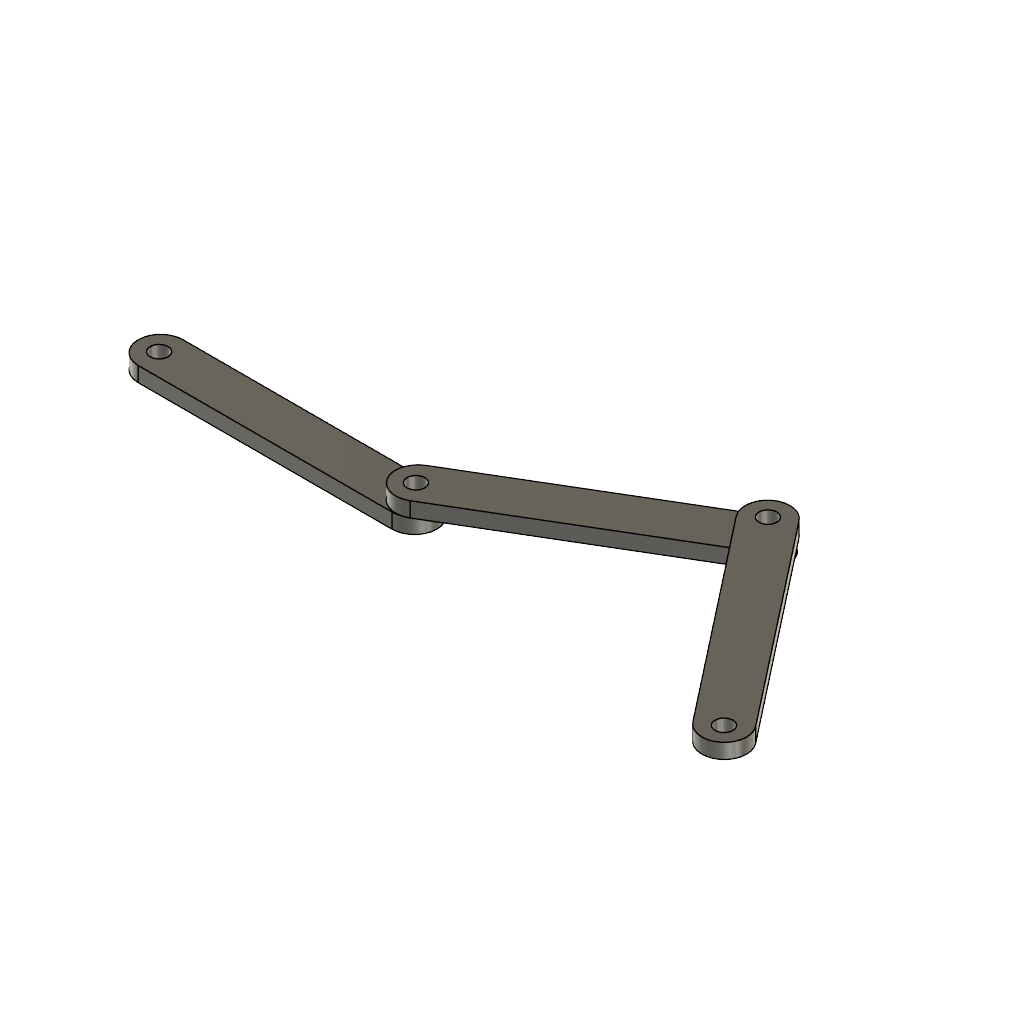
Rib (Autodesk Fusion 360 archive; units mm, degrees)
design "제목 없음"
part number: 2026-10-09-12-04-33-957
part number: 2026-10-10-00-51-56-388
Autodesk Fusion 360 part; units mm, degrees
sketch "스케치1" plane through (0, 0, 0) normal (0, 0, 1) x (1, 0, 0)
  line L0 (0, 0) -> (100, 0)
  line L1 (100, 0) -> (100, 15)
  line L2 (100, 15) -> (0, 15)
  line L3 (0, 15) -> (0, 0)
  dimension "d1" = 100
  dimension "d2" = 15
  constraint horizontal L0
  constraint vertical L1
  constraint horizontal L2
  constraint vertical L3
  constraint coincident L0.start L3.end
  measures "d1" distance of L0.start L0.end
  measures "d2" distance of L0.start L2.end
extrude "돌출1" add sketch "스케치1" along normal blind 5 makes body 1
sketch "스케치2" plane through (0, 0, 5) normal (0, 0, 1) x (-1, 0, 0)
  line L0 (0, -15) -> (0, 0)
  line L1 (0, 0) -> (-100, 0)
  line L2 (-100, 0) -> (-100, -15)
  line L3 (-100, -15) -> (0, -15)
  circle A0 centre (-7, -7.5) radius 3
  circle A1 centre (-93, -7.5) radius 3
  dimension "d5" = 6
  dimension "d6" = 7
  dimension "d7" = 7.5
  dimension "d8" = 6
  dimension "d9" = 7
  dimension "d10" = 7.5
  measures "d5" diameter of A0
  measures "d6" horizontal distance of L0.end A0.centre
  measures "d7" vertical distance of L0.end A0.centre
  measures "d8" diameter of A1
  measures "d9" horizontal distance of L1.end A1.centre
  measures "d10" vertical distance of L1.end A1.centre
extrude "돌출2" cut sketch "스케치2" against normal through all contours A0 | A1 bodies 1
fillet "필렛1" radius 7.5 4 edges at (0, 0, 2.5) (0, 15, 2.5) (100, 0, 2.5) (100, 15, 2.5) on bodies 1
copy_body "본체->구성요소1" bodies 1 removing the originals makes body 2 in component "Component'"
component "Component'" placed x (1, 0, 0) y (0, 1, 0) z (0, 0, 1) at (0, 0, 0)
component "Component'" placed x (1, 0, 0) y (0, 1, 0) z (0, 0, 1) at (86, 0, 5)
component "Component'" placed x (1, 0, 0) y (0, 1, 0) z (0, 0, 1) at (172, 0, 10)
